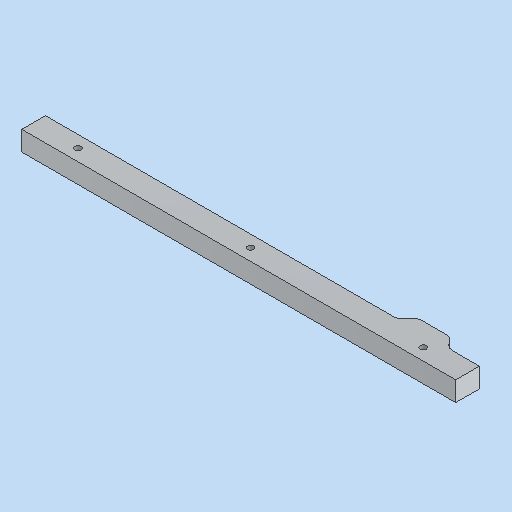
# Autodesk Inventor part: MM0948AN130_G01_111
Saved by Autodesk Inventor 2023.3 (Build 273359000, 359)
## iProperties
Created: 2023-06-22
Part Number: MM0948AN130_G01_111
Material: 3.3547 AlMg4,5Mn0,7 - AW 5083
Description: =<RBPARTNOTITLE2>
Document SubType Name: Modeling
Designer: RIC7AN
Mass: 72.6478 g
Surface Area: 104.5 cm^2
Volume: 27.3112 cm^3
Density: 2.66 g/cm^3
Appearance: Aluminium AnP
Vendor: --
RBPARTMADEOF: 10 x 17,5 x 220 (FM)
RBDRAWINGMISSINGSPEC: --
AnP_Kategorie: 1
RBPARTNOTITLE2: Anfertigungsteil
RBSURFACE: anodised colourless
RBPARTNOTITLE1: manufactured part
RBSURFACE2: eloxiert farblos
AnP_Material: =<Material>
RBMATERIAL: =<Material>
RBMATNO: =<Part Number>
RBPARTNO: SIEHE MNR
MaxAbmaße: 10 x 17,5 x 220 (FM)
Author: RIC7AN
Keywords: =<RBPARTMADEOF>
Comments: =<RBSURFACE2>
Revision Number: 01
Autodesk Inventor part; units mm, degrees
ref_plane "YZ Plane" through (0, 0, 0) normal (1, 0, 0) x (0, 1, 0)
ref_plane "XZ Plane" through (0, 0, 0) normal (0, 1, 0) x (-1, 0, 0)
ref_plane "XY Plane" through (0, 0, 0) normal (0, 0, 1) x (1, 0, 0)
sketch "Skizze1" plane through (0, 0, 0) normal (0, 0, 1) x (1, 0, 0)
  line L0 (-110, 6) -> (110, 6)
  line L1 (110, 6) -> (110, -6)
  line L2 (110, -6) -> (-110, -6)
  line L3 (-110, -6) -> (-110, 6)
  line L4 (91.5, 6) -> (71.5, 6)
  line L5 (71.5, 6) -> (71.5, 11.5)
  line L6 (71.5, 11.5) -> (91.5, 11.5)
  line L7 (91.5, 11.5) -> (91.5, 6)
  line L8 (0, 15) -> (0, -9.5) projected
  line L9 (-154, 0) -> (154, 0) projected
  line L10 (81.5, 11.5) -> (81.5, 6) construction
  point P0 (0, 0)
  point P1 (71.5, 6)
  dimension "d0" = 12
  dimension "d1" = 5.5
  dimension "d2" = 20
  dimension "d3" = 220
  dimension "d4" = 28.5
  constraints: 18 end point, 4 parallel, 2 horizontal, 2 midpoint, 2 perpendicular, 1 point on line, 2 other
  measures "d0" distance of L2.end L0.start
  measures "d1" distance of L6.end L4.start
  measures "d2" distance of L5.end L6.end
  measures "d3" distance of L1.end L2.end
  measures "d4" distance between parallel lines of L1 L10
extrude "Extrusion1" add sketch "Skizze1" along normal blind 10
fillet "Rundung1" radius 5 4 edges at (71.5, 6, 5) (71.5, 11.5, 5) (91.5, 11.5, 5) (91.5, 6, 5)
sketch "Skizze2" plane through (0, 0, 10) normal (0, 0, 1) x (1, 0, 0)
  line L0 (0, 15) -> (0, -9.5) projected
  line L1 (-154, 0) -> (154, 0) projected
  point P0 (0, 0)
  point P1 (-87.5, 0)
  point P2 (0, 0)
  point P3 (87.5, 0)
  dimension "d8" = 175
  constraints: 3 point on line, 1 midpoint, 1 symmetric about line
  measures "d8" distance of point (87.5, 0) point (-87.5, 0)
hole "Bohrung1" at (-87.5, 0, 10) at (0, 0, 10) at (87.5, 0, 10) direction (0, 0, -1) diameter 3.242 end through all thread size "M4x0.7" designation "M4" class "6H" standard "ISO Metric profile"
